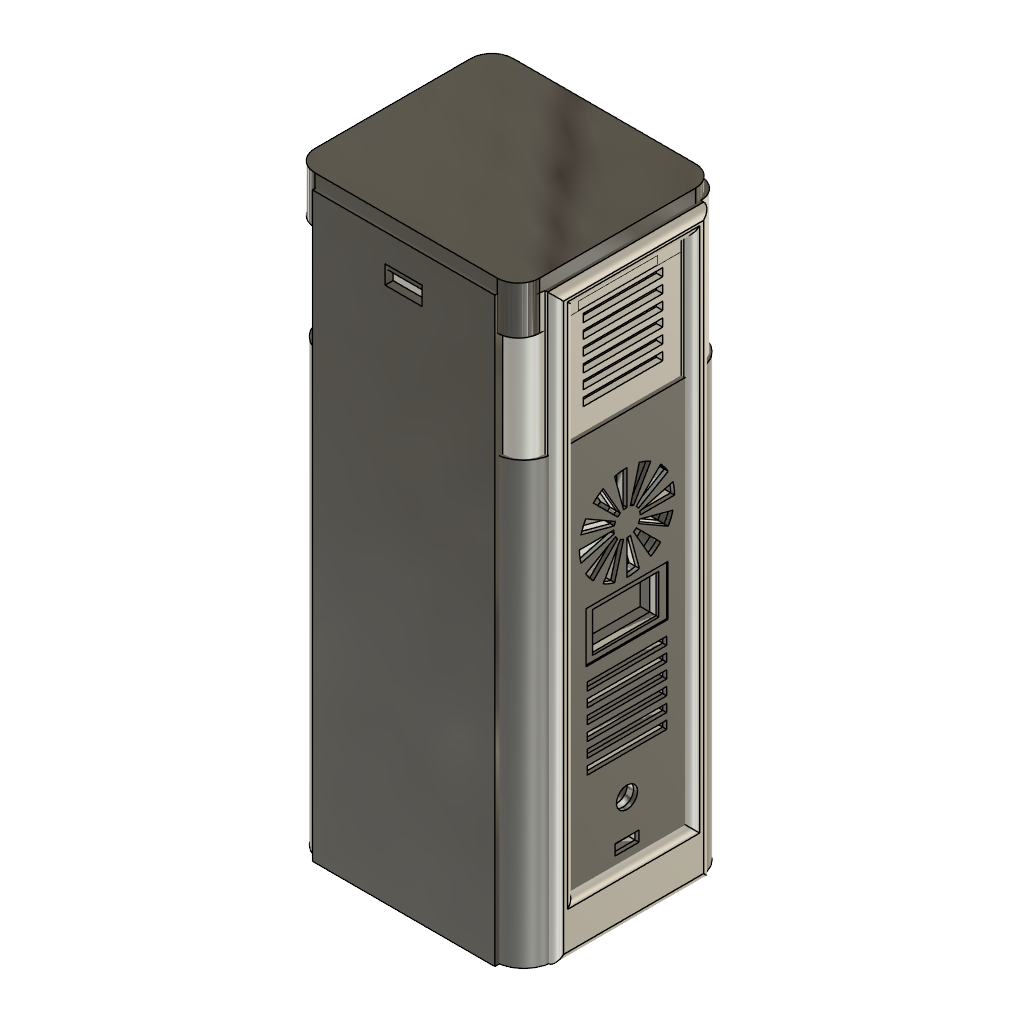
medicool (Autodesk Fusion 360 design; units mm, degrees)
part number: 2026-09-28-00-36-43-570
part number: 2026-09-28-00-40-26-390
part number: 2026-09-28-00-40-26-450
part number: 2026-09-28-00-40-26-466
part number: 2026-09-28-00-40-26-481
part number: 2026-09-28-00-40-26-496
part number: 2026-09-28-00-40-26-510
part number: 2026-09-28-00-40-26-523
part number: 2026-09-28-00-40-26-538
part number: 2026-09-28-00-40-26-553
part number: 2026-09-28-00-40-26-570
part number: 2026-09-28-00-40-26-587
part number: 2026-09-28-00-40-26-603
part number: 2026-09-28-00-40-26-620
part number: 2026-09-28-00-40-26-638
part number: 2026-09-28-00-40-26-657
Autodesk Fusion 360 part; units mm, degrees
sketch "Sketch1" plane through (0, 0, 0) normal (0, 0, 1) x (1, 0, 0) in component "Outer Shell"
  line L0 (-42.5, -37.5) -> (42.5, -37.5)
  line L1 (42.5, -37.5) -> (42.5, 37.5)
  line L2 (42.5, 37.5) -> (-42.5, 37.5)
  line L3 (-42.5, 37.5) -> (-42.5, -37.5)
extrude "Extrude1" add sketch "Sketch1" along normal blind 220 makes body 1 in component "Outer Shell"
fillet "Fillet1" radius 8 4 edges at (-42.5, 37.5, 110) (42.5, 37.5, 110) (42.5, -37.5, 110) (-42.5, -37.5, 110) on bodies 1 in component "Outer Shell"
shell "Shell1" thickness 2.4 removed faces 1 at (-11.5, 12.5, 220) on bodies 1 in component "Outer Shell"
sketch "Sketch1 (2)" plane through (0, 0, 0) normal (0, 0, 1) x (1, 0, 0) in component "Inner Medicine Chamber"
  line L0 (-29, -24) -> (29, -24)
  line L1 (29, -24) -> (29, 24)
  line L2 (29, 24) -> (-29, 24)
  line L3 (-29, 24) -> (-29, -24)
extrude "Extrude1'" add sketch "Sketch1 (2)" along normal blind 151.5 separate body makes body 2 in component "Inner Medicine Chamber"
fillet "Fillet1'" radius 4 4 edges at (-29, 24, 75.75) (29, 24, 75.75) (29, -24, 75.75) (-29, -24, 75.75) on bodies 2 in component "Inner Medicine Chamber"
shell "Shell1'" thickness 1.5 removed faces 1 at (8.3333, -8, 151.5) on bodies 2 in component "Inner Medicine Chamber"
sketch "Sketch1 (3)" plane through (0, 0, 0) normal (0, 0, 1) x (1, 0, 0) in component "Insulation Cavity"
  line L0 (-44, -39) -> (44, -39)
  line L1 (44, -39) -> (44, 39)
  line L2 (44, 39) -> (-44, 39)
  line L3 (-44, 39) -> (-44, -39)
extrude "Extrude1''" add sketch "Sketch1 (3)" along normal blind 166.5 separate body makes body 3 in component "Insulation Cavity"
fillet "Fillet1''" radius 11.5 4 edges at (-44, 39, 83.25) (44, 39, 83.25) (44, -39, 83.25) (-44, -39, 83.25) on bodies 3 in component "Insulation Cavity"
shell "Shell1''" thickness 15 removed faces 1 at (-10.8333, -13, 166.5) on bodies 3 in component "Insulation Cavity"
sketch "Sketch1 (4)" plane through (0, 0, 0) normal (0, 0, 1) x (1, 0, 0) in component "Medicine Tray"
  line L0 (-26.5, -21.5) -> (26.5, -21.5)
  line L1 (26.5, -21.5) -> (26.5, 21.5)
  line L2 (26.5, 21.5) -> (-26.5, 21.5)
  line L3 (-26.5, 21.5) -> (-26.5, -21.5)
extrude "Extrude1'''" add sketch "Sketch1 (4)" along normal blind 140 separate body makes body 4 in component "Medicine Tray"
fillet "Fillet1'''" radius 3 4 edges at (-26.5, 21.5, 70) (26.5, 21.5, 70) (26.5, -21.5, 70) (-26.5, -21.5, 70) on bodies 4 in component "Medicine Tray"
shell "Shell1'''" thickness 1.5 removed faces 1 at (7.8333, -7.1667, 140) on bodies 4 in component "Medicine Tray"
sketch "Sketch1 (5)" plane through (0, 0, 0) normal (0, 0, 1) x (1, 0, 0) in component "Insulated Lid"
  line L0 (-42.5, -37.5) -> (42.5, -37.5)
  line L1 (42.5, -37.5) -> (42.5, 37.5)
  line L2 (42.5, 37.5) -> (-42.5, 37.5)
  line L3 (-42.5, 37.5) -> (-42.5, -37.5)
extrude "Extrude1''''" add sketch "Sketch1 (5)" along normal blind 18 separate body makes body 5 in component "Insulated Lid"
fillet "Fillet1''''" radius 8 4 edges at (-42.5, 37.5, 9) (42.5, 37.5, 9) (42.5, -37.5, 9) (-42.5, -37.5, 9) on bodies 5 in component "Insulated Lid"
sketch "Sketch2" plane through (0, 0, 0) normal (0, 0, -1) x (-1, 0, 0) in component "Insulated Lid"
  arc A0 (34.5, -37.5) -> (42.5, -29.5) centre (34.5, -29.5) ccw
  line L0 (42.5, -29.5) -> (42.5, 29.5)
  arc A1 (42.5, 29.5) -> (34.5, 37.5) centre (34.5, 29.5) ccw
  line L1 (34.5, 37.5) -> (-34.5, 37.5)
  arc A2 (-34.5, 37.5) -> (-42.5, 29.5) centre (-34.5, 29.5) ccw
  line L2 (-42.5, 29.5) -> (-42.5, -29.5)
  arc A3 (-42.5, -29.5) -> (-34.5, -37.5) centre (-34.5, -29.5) ccw
  line L3 (-34.5, -37.5) -> (34.5, -37.5)
  line L4 (-39.5, -34.5) -> (39.5, -34.5)
  line L5 (39.5, -34.5) -> (39.5, 34.5)
  line L6 (39.5, 34.5) -> (-39.5, 34.5)
  line L7 (-39.5, 34.5) -> (-39.5, -34.5)
  line L8 (-36.5, -31.5) -> (36.5, -31.5)
  line L9 (36.5, -31.5) -> (36.5, 31.5)
  line L10 (36.5, 31.5) -> (-36.5, 31.5)
  line L11 (-36.5, 31.5) -> (-36.5, -31.5)
sketch "Sketch1 (6)" plane through (0, 0, 0) normal (0, 0, 1) x (1, 0, 0) in component "Cold Plate"
  line L0 (-20, -20) -> (20, -20)
  line L1 (20, -20) -> (20, 20)
  line L2 (20, 20) -> (-20, 20)
  line L3 (-20, 20) -> (-20, -20)
extrude "Extrude1'''''" add sketch "Sketch1 (6)" along normal blind 3 separate body makes body 6 in component "Cold Plate"
sketch "Sketch1 (7)" plane through (0, 0, 0) normal (0, 0, 1) x (1, 0, 0) in component "Hot Plate"
  line L0 (-20, -20) -> (20, -20)
  line L1 (20, -20) -> (20, 20)
  line L2 (20, 20) -> (-20, 20)
  line L3 (-20, 20) -> (-20, -20)
extrude "Extrude1''''''" add sketch "Sketch1 (7)" along normal blind 3 separate body makes body 7 in component "Hot Plate"
sketch "Sketch1 (8)" plane through (0, 0, 0) normal (0, 0, 1) x (1, 0, 0) in component "Peltier Mounting Frame"
  line L0 (-23, -23) -> (23, -23)
  line L1 (23, -23) -> (23, 23)
  line L2 (23, 23) -> (-23, 23)
  line L3 (-23, 23) -> (-23, -23)
  line L4 (-20, -20) -> (20, -20)
  line L5 (20, -20) -> (20, 20)
  line L6 (20, 20) -> (-20, 20)
  line L7 (-20, 20) -> (-20, -20)
extrude "Extrude1'''''''" add sketch "Sketch1 (8)" along normal blind 4.6 separate body makes body 8 in component "Peltier Mounting Frame"
sketch "Sketch1 (9)" plane through (0, 0, 0) normal (0, 0, 1) x (1, 0, 0) in component "Heatsink Mount"
  line L0 (-22, -22) -> (22, -22)
  line L1 (22, -22) -> (22, 22)
  line L2 (22, 22) -> (-22, 22)
  line L3 (-22, 22) -> (-22, -22)
extrude "Extrude1''''''''" add sketch "Sketch1 (9)" along normal blind 2 separate body makes body 9 in component "Heatsink Mount"
sketch "Sketch2 (2)" plane through (0, 0, 2) normal (0, 0, 1) x (1, 0, 0) in component "Heatsink Mount"
  line L0 (-22, 22) -> (-22, -22)
  line L1 (-22, -22) -> (22, -22)
  line L2 (22, -22) -> (22, 22)
  line L3 (22, 22) -> (-22, 22)
  line L4 (-19.8, -18.9091) -> (19.8, -18.9091)
  line L5 (19.8, -18.9091) -> (19.8, -17.9091)
  line L6 (19.8, -17.9091) -> (-19.8, -17.9091)
  line L7 (-19.8, -17.9091) -> (-19.8, -18.9091)
  line L8 (-19.8, -14.8182) -> (19.8, -14.8182)
  line L9 (19.8, -14.8182) -> (19.8, -13.8182)
  line L10 (19.8, -13.8182) -> (-19.8, -13.8182)
  line L11 (-19.8, -13.8182) -> (-19.8, -14.8182)
  line L12 (-19.8, -10.7273) -> (19.8, -10.7273)
  line L13 (19.8, -10.7273) -> (19.8, -9.7273)
  line L14 (19.8, -9.7273) -> (-19.8, -9.7273)
  line L15 (-19.8, -9.7273) -> (-19.8, -10.7273)
  line L16 (-19.8, -6.6364) -> (19.8, -6.6364)
  line L17 (19.8, -6.6364) -> (19.8, -5.6364)
  line L18 (19.8, -5.6364) -> (-19.8, -5.6364)
  line L19 (-19.8, -5.6364) -> (-19.8, -6.6364)
  line L20 (-19.8, -2.5455) -> (19.8, -2.5455)
  line L21 (19.8, -2.5455) -> (19.8, -1.5455)
  line L22 (19.8, -1.5455) -> (-19.8, -1.5455)
  line L23 (-19.8, -1.5455) -> (-19.8, -2.5455)
  line L24 (-19.8, 1.5455) -> (19.8, 1.5455)
  line L25 (19.8, 1.5455) -> (19.8, 2.5455)
  line L26 (19.8, 2.5455) -> (-19.8, 2.5455)
  line L27 (-19.8, 2.5455) -> (-19.8, 1.5455)
  line L28 (-19.8, 5.6364) -> (19.8, 5.6364)
  line L29 (19.8, 5.6364) -> (19.8, 6.6364)
  line L30 (19.8, 6.6364) -> (-19.8, 6.6364)
  line L31 (-19.8, 6.6364) -> (-19.8, 5.6364)
  line L32 (-19.8, 9.7273) -> (19.8, 9.7273)
  line L33 (19.8, 9.7273) -> (19.8, 10.7273)
  line L34 (19.8, 10.7273) -> (-19.8, 10.7273)
  line L35 (-19.8, 10.7273) -> (-19.8, 9.7273)
  line L36 (-19.8, 13.8182) -> (19.8, 13.8182)
  line L37 (19.8, 13.8182) -> (19.8, 14.8182)
  line L38 (19.8, 14.8182) -> (-19.8, 14.8182)
  line L39 (-19.8, 14.8182) -> (-19.8, 13.8182)
  line L40 (-19.8, 17.9091) -> (19.8, 17.9091)
  line L41 (19.8, 17.9091) -> (19.8, 18.9091)
  line L42 (19.8, 18.9091) -> (-19.8, 18.9091)
  line L43 (-19.8, 18.9091) -> (-19.8, 17.9091)
extrude "Extrude2" add sketch "Sketch2 (2)" along normal blind 30 contours L0 L1 L2 L3 | L4 L5 L6 L7 | L8 L9 L10 L11 | L12 L13 L14 L15 | L16 L17 L18 L19 | L20 L21 L22 L23 | L24 L25 L26 L27 | L28 L29 L30 L31 | L32 L33 L34 L35 | L36 L37 L38 L39 | L40 L41 L42 L43 bodies 9 in component "Heatsink Mount"
sketch "Sketch1 (10)" plane through (0, 0, 0) normal (0, 0, 1) x (1, 0, 0) in component "Fan Mount"
  line L0 (-20, -20) -> (20, -20)
  line L1 (20, -20) -> (20, 20)
  line L2 (20, 20) -> (-20, 20)
  line L3 (-20, 20) -> (-20, -20)
extrude "Extrude1'''''''''" add sketch "Sketch1 (10)" along normal blind 3 separate body makes body 10 in component "Fan Mount"
sketch "Sketch2 (3)" plane through (0, 0, 3) normal (0, 0, 1) x (1, 0, 0) in component "Fan Mount"
  line L0 (-20, 20) -> (-20, -20)
  line L1 (-20, -20) -> (20, -20)
  line L2 (20, -20) -> (20, 20)
  line L3 (20, 20) -> (-20, 20)
  circle A0 centre (0, 0) radius 15
  circle A1 centre (16, 16) radius 1.3
  circle A2 centre (-16, 16) radius 1.3
  circle A3 centre (16, -16) radius 1.3
  circle A4 centre (-16, -16) radius 1.3
sketch "Sketch12" plane through (0, 0, 0) normal (0, 0, 1) x (1, 0, 0) in component "Airflow Duct"
  line L0 (-24, -24) -> (24, -24)
  line L1 (24, -24) -> (24, 24)
  line L2 (24, 24) -> (-24, 24)
  line L3 (-24, 24) -> (-24, -24)
extrude "Extrude10" add sketch "Sketch12" along normal blind 44 separate body makes body 11 in component "Airflow Duct"
shell "Shell6" thickness 2 removed faces 2 at (-8, -8, 44) at (-8, -8, 0) on bodies 11 in component "Airflow Duct"
sketch "Sketch13" plane through (0, 0, 0) normal (0, 1, 0) x (1, 0, 0) in component "Airflow Duct"
  line L0 (-15, 0) -> (15, 0)
  line L1 (15, 0) -> (15, 40)
  line L2 (15, 40) -> (-15, 40)
  line L3 (-15, 40) -> (-15, 0)
extrude "Extrude11" add sketch "Sketch13" along normal mid plane 6 separate body makes body 12 in component "Airflow Duct"
move_body "Move1" bodies 12 to x (1, 0, 0) y (0, 1, 0) z (0, 0, 1) at (0, -23, 0) in component "Airflow Duct"
combine "Combine1" operation cut target body 11 tool bodies 12 in component "Airflow Duct"
sketch "Sketch1 (11)" plane through (0, 0, 0) normal (0, 0, 1) x (1, 0, 0) in component "Electronics Tray"
  line L0 (-38.1, -33.1) -> (38.1, -33.1)
  line L1 (38.1, -33.1) -> (38.1, 33.1)
  line L2 (38.1, 33.1) -> (-38.1, 33.1)
  line L3 (-38.1, 33.1) -> (-38.1, -33.1)
extrude "Extrude1''''''''''" add sketch "Sketch1 (11)" along normal blind 1.5 separate body makes body 13 in component "Electronics Tray"
sketch "Sketch2 (4)" plane through (0, 0, 1.5) normal (0, 0, 1) x (1, 0, 0) in component "Electronics Tray"
  line L0 (-38.1, 33.1) -> (-38.1, -33.1)
  line L1 (-38.1, -33.1) -> (38.1, -33.1)
  line L2 (38.1, -33.1) -> (38.1, 33.1)
  line L3 (38.1, 33.1) -> (-38.1, 33.1)
  circle A0 centre (27, 17) radius 3
  circle A1 centre (-27, 17) radius 3
  circle A2 centre (27, -17) radius 3
  circle A3 centre (-27, -17) radius 3
extrude "Extrude2'" add sketch "Sketch2 (4)" along normal blind 6 contours L0 L1 L2 L3 | A0 | A1 | A2 | A3 bodies 13 in component "Electronics Tray"
sketch "Sketch1 (12)" plane through (0, 0, 0) normal (0, 0, 1) x (1, 0, 0) in component "Battery Tray"
  line L0 (-27.5, -20) -> (27.5, -20)
  line L1 (27.5, -20) -> (27.5, 20)
  line L2 (27.5, 20) -> (-27.5, 20)
  line L3 (-27.5, 20) -> (-27.5, -20)
extrude "Extrude1'''''''''''" add sketch "Sketch1 (12)" along normal blind 20 separate body makes body 14 in component "Battery Tray"
shell "Shell1''''" thickness 1.5 removed faces 1 at (-9.1667, 6.6667, 20) on bodies 14 in component "Battery Tray"
sketch "Sketch3" plane through (0, 0, 0) normal (0, 1, 0) x (1, 0, 0) in component "Battery Tray"
  line L0 (-1, 6) -> (1, 6)
  line L1 (1, 6) -> (1, 14)
  line L2 (1, 14) -> (-1, 14)
  line L3 (-1, 14) -> (-1, 6)
extrude "Extrude3" add sketch "Sketch3" along normal mid plane 4.5 separate body makes body 15 in component "Battery Tray"
move_body "Move1'" bodies 15 to x (1, 0, 0) y (0, 1, 0) z (0, 0, 1) at (0, -19.25, 0) in component "Battery Tray"
combine "Combine1'" operation cut target body 14 tool bodies 15 in component "Battery Tray"
sketch "Sketch1 (13)" plane through (0, 0, 0) normal (0, 0, 1) x (1, 0, 0) in component "Front Control Panel"
  line L0 (-38.25, -20.25) -> (38.25, -20.25)
  line L1 (38.25, -20.25) -> (38.25, 20.25)
  line L2 (38.25, 20.25) -> (-38.25, 20.25)
  line L3 (-38.25, 20.25) -> (-38.25, -20.25)
extrude "Extrude1''''''''''''" add sketch "Sketch1 (13)" along normal blind 2.4 separate body makes body 16 in component "Front Control Panel"
sketch "Sketch2 (5)" plane through (0, 0, 0) normal (0, 0, 1) x (1, 0, 0) in component "Front Control Panel"
  line L0 (-12.5, 10) -> (12.5, 10)
  line L1 (12.5, 10) -> (12.5, 25)
  line L2 (12.5, 25) -> (-12.5, 25)
  line L3 (-12.5, 25) -> (-12.5, 10)
  line L4 (-4.5, -15) -> (4.5, -15)
  line L5 (4.5, -15) -> (4.5, -11)
  line L6 (4.5, -11) -> (-4.5, -11)
  line L7 (-4.5, -11) -> (-4.5, -15)
  circle A0 centre (15, -3) radius 4
  circle A1 centre (-15, 2) radius 1.5
  circle A2 centre (-15, -2) radius 1.5
extrude "Extrude5" cut sketch "Sketch2 (5)" along normal blind 2.4 bodies 1 in component "Outer Shell"
extrude "Extrude5'" cut sketch "Sketch2 (5)" along normal blind 2.4 bodies 3 in component "Insulation Cavity"
extrude "Extrude3'" cut sketch "Sketch2 (5)" along normal blind 2.4 bodies 2 in component "Inner Medicine Chamber"
extrude "Extrude3''" cut sketch "Sketch2 (5)" along normal blind 2.4 bodies 4 in component "Medicine Tray"
extrude "Extrude6" cut sketch "Sketch2 (5)" along normal blind 2.4 bodies 5 in component "Insulated Lid"
extrude "Extrude3'''" cut sketch "Sketch2 (5)" along normal blind 2.4 bodies 6 in component "Cold Plate"
extrude "Extrude3''''" cut sketch "Sketch2 (5)" along normal blind 2.4 bodies 8 in component "Peltier Mounting Frame"
extrude "Extrude3'''''" cut sketch "Sketch2 (5)" along normal blind 2.4 bodies 7 in component "Hot Plate"
extrude "Extrude4" cut sketch "Sketch2 (5)" along normal blind 2.4 bodies 9 in component "Heatsink Mount"
extrude "Extrude4'" cut sketch "Sketch2 (5)" along normal blind 2.4 bodies 10 in component "Fan Mount"
extrude "Extrude12" cut sketch "Sketch2 (5)" along normal blind 2.4 bodies 11 in component "Airflow Duct"
extrude "Extrude3''''''" cut sketch "Sketch2 (5)" along normal blind 2.4 bodies 13 in component "Electronics Tray"
extrude "Extrude4''" cut sketch "Sketch2 (5)" along normal blind 2.4 bodies 14 in component "Battery Tray"
extrude "Extrude2''" cut sketch "Sketch2 (5)" along normal blind 2.4 bodies 16 in component "Front Control Panel"
sketch "Sketch1 (14)" plane through (0, 0, 0) normal (0, 0, 1) x (1, 0, 0) in component "Service Panels"
  line L0 (-41.25, -23.25) -> (41.25, -23.25)
  line L1 (41.25, -23.25) -> (41.25, 23.25)
  line L2 (41.25, 23.25) -> (-41.25, 23.25)
  line L3 (-41.25, 23.25) -> (-41.25, -23.25)
extrude "Extrude1'''''''''''''" add sketch "Sketch1 (14)" along normal blind 2.4 separate body makes body 17 in component "Service Panels"
fillet "Fillet1'''''" radius 3 4 edges at (-41.25, 23.25, 1.2) (41.25, 23.25, 1.2) (41.25, -23.25, 1.2) (-41.25, -23.25, 1.2) on bodies 17 in component "Service Panels"
sketch "Sketch2 (6)" plane through (0, 0, 0) normal (0, 0, 1) x (1, 0, 0) in component "Service Panels"
  circle A0 centre (37.25, 19.25) radius 1.3
  circle A1 centre (-37.25, 19.25) radius 1.3
  circle A2 centre (37.25, -19.25) radius 1.3
  circle A3 centre (-37.25, -19.25) radius 1.3
move_body "Move1''" bodies 5 to x (1, 0, 0) y (0, 1, 0) z (0, 0, 1) at (0, 0, 202) in component "Insulated Lid"
sketch "ThermalBulgeSketch" plane through (42.5, 0, 0) normal (1, 0, 0) x (0, 1, 0) in component "Outer Shell"
  line L0 (-29.5, 220) -> (-29.5, 0)
  line L1 (-29.5, 0) -> (29.5, 0)
  line L2 (29.5, 0) -> (29.5, 220)
  line L3 (29.5, 220) -> (-29.5, 220)
  line L4 (-22, 20) -> (22, 20)
  line L5 (22, 20) -> (22, 213)
  line L6 (22, 213) -> (-22, 213)
  line L7 (-22, 213) -> (-22, 20)
extrude "Extrude11'" add sketch "ThermalBulgeSketch" along normal blind 4 bodies 1 in component "Outer Shell"
fillet "Fillet2" radius 3 8 edges at (46.5, -22, 116.5) (46.5, 0, 213) (46.5, 22, 116.5) (46.5, 0, 20) (46.5, 0, 220) (46.5, -29.5, 110) (46.5, 0, 0) (46.5, 29.5, 110) on bodies 1 in component "Outer Shell"
sketch "LatchTabSketch" plane through (0, -37.5, 0) normal (0, -1, 0) x (1, 0, 0) in component "Outer Shell"
  line L0 (-34.5, 220) -> (-34.5, 0)
  line L1 (-34.5, 0) -> (34.5, 0)
  line L2 (34.5, 0) -> (34.5, 220)
  line L3 (34.5, 220) -> (-34.5, 220)
  line L4 (-7, 202.5) -> (7, 202.5)
  line L5 (7, 202.5) -> (7, 209.5)
  line L6 (7, 209.5) -> (-7, 209.5)
  line L7 (-7, 209.5) -> (-7, 202.5)
extrude "Extrude12'" add sketch "LatchTabSketch" along normal blind 3 bodies 1 in component "Outer Shell"
ref_plane "WorkPlane1" through (46.5, 0, 0) normal (1, 0, 0) x (0, 1, 0) in component "Outer Shell"
sketch "ThermalVentSketch3" plane through (46.5, 0, 0) normal (1, 0, 0) x (0, 0, -1) in component "Outer Shell"
  line L0 (-202.25, -15) -> (-205.25, -15)
  line L1 (-205.25, -15) -> (-205.25, 15)
  line L2 (-205.25, 15) -> (-202.25, 15)
  line L3 (-202.25, 15) -> (-202.25, -15)
  line L4 (-196.75, -15) -> (-199.75, -15)
  line L5 (-199.75, -15) -> (-199.75, 15)
  line L6 (-199.75, 15) -> (-196.75, 15)
  line L7 (-196.75, 15) -> (-196.75, -15)
  line L8 (-191.25, -15) -> (-194.25, -15)
  line L9 (-194.25, -15) -> (-194.25, 15)
  line L10 (-194.25, 15) -> (-191.25, 15)
  line L11 (-191.25, 15) -> (-191.25, -15)
  line L12 (-185.75, -15) -> (-188.75, -15)
  line L13 (-188.75, -15) -> (-188.75, 15)
  line L14 (-188.75, 15) -> (-185.75, 15)
  line L15 (-185.75, 15) -> (-185.75, -15)
  line L16 (-180.25, -15) -> (-183.25, -15)
  line L17 (-183.25, -15) -> (-183.25, 15)
  line L18 (-183.25, 15) -> (-180.25, 15)
  line L19 (-180.25, 15) -> (-180.25, -15)
  line L20 (-174.75, -15) -> (-177.75, -15)
  line L21 (-177.75, -15) -> (-177.75, 15)
  line L22 (-177.75, 15) -> (-174.75, 15)
  line L23 (-174.75, 15) -> (-174.75, -15)
  line L24 (-82.25, -15) -> (-85.25, -15)
  line L25 (-85.25, -15) -> (-85.25, 15)
  line L26 (-85.25, 15) -> (-82.25, 15)
  line L27 (-82.25, 15) -> (-82.25, -15)
  line L28 (-76.75, -15) -> (-79.75, -15)
  line L29 (-79.75, -15) -> (-79.75, 15)
  line L30 (-79.75, 15) -> (-76.75, 15)
  line L31 (-76.75, 15) -> (-76.75, -15)
  line L32 (-71.25, -15) -> (-74.25, -15)
  line L33 (-74.25, -15) -> (-74.25, 15)
  line L34 (-74.25, 15) -> (-71.25, 15)
  line L35 (-71.25, 15) -> (-71.25, -15)
  line L36 (-65.75, -15) -> (-68.75, -15)
  line L37 (-68.75, -15) -> (-68.75, 15)
  line L38 (-68.75, 15) -> (-65.75, 15)
  line L39 (-65.75, 15) -> (-65.75, -15)
  line L40 (-60.25, -15) -> (-63.25, -15)
  line L41 (-63.25, -15) -> (-63.25, 15)
  line L42 (-63.25, 15) -> (-60.25, 15)
  line L43 (-60.25, 15) -> (-60.25, -15)
  line L44 (-54.75, -15) -> (-57.75, -15)
  line L45 (-57.75, -15) -> (-57.75, 15)
  line L46 (-57.75, 15) -> (-54.75, 15)
  line L47 (-54.75, 15) -> (-54.75, -15)
  line L48 (-130, 5) -> (-130, 18)
  line L49 (-131.2941, 4.8296) -> (-134.6587, 17.3867)
  arc A0 (-130, 18) -> (-134.6587, 17.3867) centre (-130, 0) ccw
  arc A1 (-130, 5) -> (-131.2941, 4.8296) centre (-130, 0) ccw
  line L50 (-132.5, 4.3301) -> (-139, 15.5885)
  line L51 (-133.5355, 3.5355) -> (-142.7279, 12.7279)
  arc A2 (-139, 15.5885) -> (-142.7279, 12.7279) centre (-130, 0) ccw
  arc A3 (-132.5, 4.3301) -> (-133.5355, 3.5355) centre (-130, 0) ccw
  line L52 (-134.3301, 2.5) -> (-145.5885, 9)
  line L53 (-134.8296, 1.2941) -> (-147.3867, 4.6587)
  arc A4 (-145.5885, 9) -> (-147.3867, 4.6587) centre (-130, 0) ccw
  arc A5 (-134.3301, 2.5) -> (-134.8296, 1.2941) centre (-130, 0) ccw
  line L54 (-135, 0) -> (-148, 0)
  line L55 (-134.8296, -1.2941) -> (-147.3867, -4.6587)
  arc A6 (-148, 0) -> (-147.3867, -4.6587) centre (-130, 0) ccw
  arc A7 (-135, 0) -> (-134.8296, -1.2941) centre (-130, 0) ccw
  line L56 (-134.3301, -2.5) -> (-145.5885, -9)
  line L57 (-133.5355, -3.5355) -> (-142.7279, -12.7279)
  arc A8 (-145.5885, -9) -> (-142.7279, -12.7279) centre (-130, 0) ccw
  arc A9 (-134.3301, -2.5) -> (-133.5355, -3.5355) centre (-130, 0) ccw
  line L58 (-132.5, -4.3301) -> (-139, -15.5885)
  line L59 (-131.2941, -4.8296) -> (-134.6587, -17.3867)
  arc A10 (-139, -15.5885) -> (-134.6587, -17.3867) centre (-130, 0) ccw
  arc A11 (-132.5, -4.3301) -> (-131.2941, -4.8296) centre (-130, 0) ccw
  line L60 (-130, -5) -> (-130, -18)
  line L61 (-128.7059, -4.8296) -> (-125.3413, -17.3867)
  arc A12 (-130, -18) -> (-125.3413, -17.3867) centre (-130, 0) ccw
  arc A13 (-130, -5) -> (-128.7059, -4.8296) centre (-130, 0) ccw
  line L62 (-127.5, -4.3301) -> (-121, -15.5885)
  line L63 (-126.4645, -3.5355) -> (-117.2721, -12.7279)
  arc A14 (-121, -15.5885) -> (-117.2721, -12.7279) centre (-130, 0) ccw
  arc A15 (-127.5, -4.3301) -> (-126.4645, -3.5355) centre (-130, 0) ccw
  line L64 (-125.6699, -2.5) -> (-114.4115, -9)
  line L65 (-125.1704, -1.2941) -> (-112.6133, -4.6587)
  arc A16 (-114.4115, -9) -> (-112.6133, -4.6587) centre (-130, 0) ccw
  arc A17 (-125.6699, -2.5) -> (-125.1704, -1.2941) centre (-130, 0) ccw
  line L66 (-125, 0) -> (-112, 0)
  line L67 (-125.1704, 1.2941) -> (-112.6133, 4.6587)
  arc A18 (-112, 0) -> (-112.6133, 4.6587) centre (-130, 0) ccw
  arc A19 (-125, 0) -> (-125.1704, 1.2941) centre (-130, 0) ccw
  line L68 (-125.6699, 2.5) -> (-114.4115, 9)
  line L69 (-126.4645, 3.5355) -> (-117.2721, 12.7279)
  arc A20 (-114.4115, 9) -> (-117.2721, 12.7279) centre (-130, 0) ccw
  arc A21 (-125.6699, 2.5) -> (-126.4645, 3.5355) centre (-130, 0) ccw
  line L70 (-127.5, 4.3301) -> (-121, 15.5885)
  line L71 (-128.7059, 4.8296) -> (-125.3413, 17.3867)
  arc A22 (-121, 15.5885) -> (-125.3413, 17.3867) centre (-130, 0) ccw
  arc A23 (-127.5, 4.3301) -> (-128.7059, 4.8296) centre (-130, 0) ccw
  circle A24 centre (-40, 0) radius 4
  line L72 (-23, -4.5) -> (-27, -4.5)
  line L73 (-27, -4.5) -> (-27, 4.5)
  line L74 (-27, 4.5) -> (-23, 4.5)
  line L75 (-23, 4.5) -> (-23, -4.5)
extrude "Extrude13" cut sketch "ThermalVentSketch3" along normal mid plane 20 bodies 1 in component "Outer Shell"
extrude "Extrude10'" cut sketch "ThermalVentSketch3" along normal mid plane 20 bodies 3 in component "Insulation Cavity"
extrude "Extrude9" cut sketch "ThermalVentSketch3" along normal mid plane 20 bodies 5 in component "Insulated Lid"
sketch "DisplayBezelSketch" plane through (46.5, 0, 0) normal (1, 0, 0) x (0, 0, -1) in component "Outer Shell"
  line L0 (-90.5, -15.5) -> (-109.5, -15.5)
  line L1 (-109.5, -15.5) -> (-109.5, 15.5)
  line L2 (-109.5, 15.5) -> (-90.5, 15.5)
  line L3 (-90.5, 15.5) -> (-90.5, -15.5)
extrude "Extrude11''" cut sketch "DisplayBezelSketch" along normal mid plane 6 bodies 3 in component "Insulation Cavity"
sketch "DisplayWindowSketch" plane through (46.5, 0, 0) normal (1, 0, 0) x (0, 0, -1) in component "Outer Shell"
  line L0 (-92.5, -12.5) -> (-107.5, -12.5)
  line L1 (-107.5, -12.5) -> (-107.5, 12.5)
  line L2 (-107.5, 12.5) -> (-92.5, 12.5)
  line L3 (-92.5, 12.5) -> (-92.5, -12.5)
extrude "Extrude14" cut sketch "DisplayWindowSketch" along normal mid plane 20 bodies 1 in component "Outer Shell"
extrude "Extrude12''" cut sketch "DisplayWindowSketch" along normal mid plane 20 bodies 3 in component "Insulation Cavity"
component "Outer Shell" placed x (1, 0, 0) y (0, 1, 0) z (0, 0, 1) at (0, 0, 0)
component "Insulation Cavity" placed x (1, 0, 0) y (0, 1, 0) z (0, 0, 1) at (0, 0, 0)
component "Inner Medicine Chamber" placed x (1, 0, 0) y (0, 1, 0) z (0, 0, 1) at (0, 0, 0)
component "Medicine Tray" placed x (1, 0, 0) y (0, 1, 0) z (0, 0, 1) at (0, 0, 0)
component "Insulated Lid" placed x (1, 0, 0) y (0, 1, 0) z (0, 0, 1) at (0, 0, 0)
component "Cold Plate" placed x (1, 0, 0) y (0, 1, 0) z (0, 0, 1) at (0, 0, 0)
component "Peltier Mounting Frame" placed x (1, 0, 0) y (0, 1, 0) z (0, 0, 1) at (0, 0, 0)
component "Hot Plate" placed x (1, 0, 0) y (0, 1, 0) z (0, 0, 1) at (0, 0, 0)
component "Heatsink Mount" placed x (1, 0, 0) y (0, 1, 0) z (0, 0, 1) at (0, 0, 0)
component "Fan Mount" placed x (1, 0, 0) y (0, 1, 0) z (0, 0, 1) at (0, 0, 0)
component "Airflow Duct" placed x (1, 0, 0) y (0, 1, 0) z (0, 0, 1) at (0, 0, 0)
component "Electronics Tray" placed x (1, 0, 0) y (0, 1, 0) z (0, 0, 1) at (0, 0, 0)
component "Battery Tray" placed x (1, 0, 0) y (0, 1, 0) z (0, 0, 1) at (0, 0, 0)
component "Front Control Panel" placed x (1, 0, 0) y (0, 1, 0) z (0, 0, 1) at (0, 0, 0)
component "Service Panels" placed x (1, 0, 0) y (0, 1, 0) z (0, 0, 1) at (0, 0, 0)
component "medicool" placed x (1, 0, 0) y (0, 1, 0) z (0, 0, 1) at (0, 0, 0) in component "Fan Mount"
equation "overall_height = 220 mm" comment "Overall device height"
equation "overall_width = 85 mm" comment "Overall device width (front face)"
equation "overall_depth = 75 mm" comment "Overall device depth"
equation "corner_fillet_radius = 8 mm" comment "External corner rounding radius"
equation "shell_wall_thickness = 2.4 mm" comment "Outer 3D printed shell wall thickness"
equation "shell_top_flange_height = 6 mm" comment "Flange height at shell top opening"
equation "insulation_thickness = 15 mm" comment "Insulation cavity thickness around chamber"
equation "chamber_liner_thickness = 1.5 mm" comment "Inner medicine chamber liner wall thickness"
equation "chamber_height = 150 mm" comment "Medicine chamber internal height"
equation "chamber_width = 55 mm" comment "Medicine chamber internal width"
equation "chamber_depth = 45 mm" comment "Medicine chamber internal depth"
equation "chamber_corner_fillet = 4 mm" comment "Internal chamber corner fillet radius"
equation "tray_wall_thickness = 1.5 mm" comment "Removable medicine tray wall thickness"
equation "tray_height = 140 mm" comment "Removable medicine tray height"
equation "tray_clearance = 1 mm" comment "Clearance between tray and chamber liner"
equation "lid_thickness = 18 mm" comment "Insulated lid overall thickness"
equation "lid_gasket_groove_width = 3 mm" comment "Gasket groove width around lid seal"
equation "lid_gasket_groove_depth = 2 mm" comment "Gasket groove depth around lid seal"
equation "lid_latch_engagement = 4 mm" comment "Latch engagement depth for lid lock"
equation "cold_plate_thickness = 3 mm" comment "Cold plate thickness, chamber side of Peltier"
equation "cold_plate_width = 40 mm" comment "Cold plate width"
equation "cold_plate_height = 40 mm" comment "Cold plate height"
equation "hot_plate_thickness = 3 mm" comment "Hot plate thickness, heatsink side of Peltier"
equation "hot_plate_width = 40 mm" comment "Hot plate width"
equation "hot_plate_height = 40 mm" comment "Hot plate height"
equation "peltier_width = 40 mm" comment "Peltier module width (TEC1-12706 class)"
equation "peltier_depth = 40 mm" comment "Peltier module depth"
equation "peltier_height = 4 mm" comment "Peltier module height/thickness"
equation "tim_gap_thickness = 0.3 mm" comment "Thermal interface material gap, per interface"
equation "peltier_frame_thickness = 3 mm" comment "Peltier mounting frame wall thickness"
equation "peltier_compression_travel = 1.5 mm" comment "Spring/standoff compression travel for even clamping"
equation "heatsink_width = 44 mm" comment "Heatsink width"
equation "heatsink_depth = 44 mm" comment "Heatsink depth"
equation "heatsink_height = 30 mm" comment "Heatsink fin stack height"
equation "heatsink_fin_count = 10" comment "Number of heatsink fins"
equation "heatsink_fin_thickness = 1 mm" comment "Heatsink fin thickness"
equation "fan_width = 40 mm" comment "Fan width, standard 40mm class"
equation "fan_depth = 40 mm" comment "Fan depth"
equation "fan_thickness = 10 mm" comment "Fan thickness"
equation "fan_hub_diameter = 30 mm" comment "Fan hub/blade opening diameter"
equation "fan_mount_hole_spacing = 32 mm" comment "Fan mounting hole spacing"
equation "fan_grille_thickness = 2 mm" comment "Removable fan grille thickness"
equation "duct_wall_thickness = 2 mm" comment "Airflow duct wall thickness"
equation "duct_clearance = 2 mm" comment "Clearance around heatsink inside duct"
equation "intake_vent_width = 30 mm" comment "Intake vent opening width"
equation "intake_vent_height = 40 mm" comment "Intake vent opening height"
equation "exhaust_vent_width = 30 mm" comment "Exhaust vent opening width"
equation "exhaust_vent_height = 40 mm" comment "Exhaust vent opening height"
equation "electronics_compartment_height = 45 mm" comment "Lower electronics compartment height"
equation "electronics_tray_thickness = 1.5 mm" comment "Electronics tray shelf thickness"
equation "pcb_width = 60 mm" comment "Main PCB / ESP32 controller board width"
equation "pcb_depth = 40 mm" comment "Main PCB depth"
equation "pcb_standoff_height = 6 mm" comment "PCB mounting standoff height"
equation "display_cutout_width = 25 mm" comment "Front panel display cutout width"
equation "display_cutout_height = 15 mm" comment "Front panel display cutout height"
equation "usb_c_cutout_width = 9 mm" comment "USB-C connector cutout width"
equation "usb_c_cutout_height = 4 mm" comment "USB-C connector cutout height"
equation "battery_compartment_width = 55 mm" comment "Battery tray compartment width, placeholder"
equation "battery_compartment_depth = 40 mm" comment "Battery tray compartment depth, placeholder"
equation "battery_compartment_height = 20 mm" comment "Battery tray compartment height, placeholder"
equation "battery_tray_wall_thickness = 1.5 mm" comment "Removable battery tray wall thickness"
equation "battery_vent_slot_width = 2 mm" comment "Battery compartment ventilation slot width"
equation "screw_boss_diameter = 6 mm" comment "Screw boss outer diameter"
equation "screw_hole_diameter = 2.6 mm" comment "Screw clearance hole diameter, M3 class"
equation "heatset_insert_diameter = 3.7 mm" comment "Heat-set insert pilot hole diameter, M3 class"
equation "heatset_insert_depth = 5 mm" comment "Heat-set insert pilot hole depth"
equation "service_panel_thickness = 2.4 mm" comment "Service/access panel thickness"
equation "service_panel_overlap = 3 mm" comment "Service panel lip overlap onto shell"
named bodies: "Outer Shell Body", "Chamber Liner Body", "Insulation Cavity Body", "Medicine Tray Body", "Insulated Lid Body", "Cold Plate Body", "Hot Plate Body", "Peltier Mounting Frame Body", "Heatsink Base", "Fan Mount Plate", "Airflow Duct Body", "IntakeVentTool", "Electronics Tray Shelf", "Battery Tray Body", "VentSlotTool1", "Front Control Panel Body", "Service Panel Body"
